831007_P01_HARDWARE-MITRE-PLATE-TABULATED_CAD (Autodesk Fusion 360 design; units mm, degrees)
description: HARDWARE - MITRE PLATE - 20 X 40 - 45 DEG - 2.0 STEEL | Tấm đệm góc vát - thép 2.0 | rev P01 | UNITS MM; MATERIAL S280GD+Z (EN 10346) OR SGC400, Z100, 2.0 SHEET; ISO 2768-m; THICKNESS 2.0 +-0.1; laser cut, no drawing (D-89 part 4); joints register H-40 to H-42; PROPOSED
part number: 831007
Autodesk Fusion 360 part; units mm, degrees
sketch "SKETCH - PLATE OUTLINE" plane through (0, 0, 0) normal (0, 0, 1) x (1, 0, 0)
  line L0 (1.75, 0) -> (28.25, 0)
  line L1 (28.25, 0) -> (28.25, 40)
  line L2 (28.25, 40) -> (1.75, 40)
  line L3 (1.75, 40) -> (1.75, 0)
  line L4 (0, 0) -> (1.75, 0) construction
  dimension "d12" = 1.75
  dimension "d13" = 26.5
  dimension "d14" = 40
  constraint horizontal L4
  constraint horizontal L0
  constraint vertical L1
  constraint horizontal L2
  constraint vertical L3
  measures "d12" horizontal distance of L4.start L0.start
  measures "d13" horizontal distance of L0.start L0.end
  measures "d14" vertical distance of L0.end L1.end
extrude "EXTRUDE - PLATE, SYMMETRIC ON THE MITRE PLANE" add sketch "SKETCH - PLATE OUTLINE" along normal mid plane 2
equation "tube_a = 20 mm" comment "CONFIRMED: the narrower member's width in the frame's plane, 20 or 40 (D-16, R-J3)"
equation "tube_b = 20 mm" comment "CONFIRMED: the other member's width in the frame's plane, 20 or 40 (D-16, R-J3)"
equation "plate_len = 26.5 mm" comment "CALCULATION: the laser-cut blank's length along the mitre line, to 0.1: 26.5 (831007), 41.5 (831008), 54.8 (831009) (frame_steel_check.py PLATE_BLANKS)"
equation "plate_d = 40 mm" comment "CONFIRMED: the frame's depth across the wall, 40 (D-16, D-42)"
equation "plate_t = 2.0 mm" comment "PROPOSED: at least 1.5 x the 1.2 mm rails, a stiffened knee (J-FRAME-01)"
equation "plate_mitre = sqrt(tube_a * tube_a + tube_b * tube_b)" comment "CALCULATION: the mitre line from the frame's outer corner to its inner corner; the blank lies on it"
equation "plate_x0 = 1.75 mm" comment "CALCULATION: where the blank starts along the mitre line from the frame's outer corner, so its square ends sit 0.5 inside the frame's faces on both plate faces (the Lead's steer 2026-11-01): 1.75 at 45 deg (831007, 831009), 3.15 at 831008 (frame_steel_check.py PLATE_BLANKS)"
equation "d12 = plate_x0"
equation "d13 = plate_len"
equation "d14 = plate_d"
equation "d15 = plate_t"
named bodies: "MITRE PLATE"
